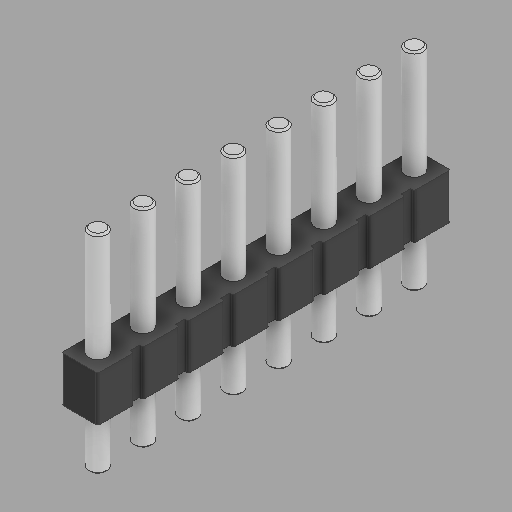
# Autodesk Inventor part: IMU_pin
Saved by Autodesk Inventor 2025 (Build 290162000, 162)
## iProperties
Created: 2024-11-11
Part Number: IMU_pin
Material: 일반
Document SubType Name: Modeling
Designer: OSB
Density: 1 g/cm^3
Appearance: 기본값
Author: OSB
Autodesk Inventor part; units mm, degrees
ref_plane "YZ Plane" through (0, 0, 0) normal (1, 0, 0) x (0, 1, 0)
ref_plane "XZ Plane" through (0, 0, 0) normal (0, 1, 0) x (-1, 0, 0)
ref_plane "XY Plane" through (0, 0, 0) normal (0, 0, 1) x (1, 0, 0)
sketch "스케치1" plane through (0, 0, 0) normal (0, 0, 1) x (1, 0, 0)
  circle A0 centre (0, 0) radius 0.5
  line L0 (0.9, -1) -> (-0.9, -1)
  line L1 (-1, -0.9) -> (-1, 0.9)
  line L2 (-0.9, 1) -> (0.9, 1)
  line L3 (1, 0.9) -> (1, -0.9)
  line L4 (1, -1) -> (-1, 1) construction
  line L5 (-1, -1) -> (1, 1) construction
  arc A1 (-0.9, 1) -> (-1, 0.9) centre (-0.9, 0.9) ccw
  arc A2 (-1, -0.9) -> (-0.9, -1) centre (-0.9, -0.9) ccw
  arc A3 (0.9, -1) -> (1, -0.9) centre (0.9, -0.9) ccw
  arc A4 (1, 0.9) -> (0.9, 1) centre (0.9, 0.9) ccw
  line L6 (-1, -0.8) -> (-1.5, -0.8)
  line L7 (-1, 0.8) -> (-1.5, 0.8)
  line L8 (-1.6, -1) -> (-3.4, -1)
  line L9 (-3.5, 0.8) -> (-4, 0.8)
  arc A5 (-1.6, -1) -> (-1.5, -0.9) centre (-1.6, -0.9) ccw
  arc A6 (-3.5, -0.9) -> (-3.4, -1) centre (-3.4, -0.9) ccw
  circle A7 centre (-2.5, 0) radius 0.5
  line L10 (-3.5, -0.8) -> (-4, -0.8)
  line L11 (-3.5, -0.9) -> (-3.5, 0.9)
  line L12 (-1.5, 0.9) -> (-1.5, -0.9)
  line L13 (-3.4, 1) -> (-1.6, 1)
  arc A8 (-3.4, 1) -> (-3.5, 0.9) centre (-3.4, 0.9) ccw
  arc A9 (-1.5, 0.9) -> (-1.6, 1) centre (-1.6, 0.9) ccw
  line L14 (-1.5, -1) -> (-3.5, 1) construction
  line L15 (-3.5, -1) -> (-1.5, 1) construction
  line L16 (-4.1, -1) -> (-5.9, -1)
  line L17 (-6, 0.8) -> (-6.5, 0.8)
  arc A10 (-4.1, -1) -> (-4, -0.9) centre (-4.1, -0.9) ccw
  arc A11 (-6, -0.9) -> (-5.9, -1) centre (-5.9, -0.9) ccw
  circle A12 centre (-5, 0) radius 0.5
  line L18 (-6, -0.8) -> (-6.5, -0.8)
  line L19 (-6, -0.9) -> (-6, 0.9)
  line L20 (-4, 0.9) -> (-4, -0.9)
  line L21 (-5.9, 1) -> (-4.1, 1)
  arc A13 (-5.9, 1) -> (-6, 0.9) centre (-5.9, 0.9) ccw
  arc A14 (-4, 0.9) -> (-4.1, 1) centre (-4.1, 0.9) ccw
  line L22 (-4, -1) -> (-6, 1) construction
  line L23 (-6, -1) -> (-4, 1) construction
  line L24 (-6.6, -1) -> (-8.4, -1)
  line L25 (-8.5, 0.8) -> (-9, 0.8)
  arc A15 (-6.6, -1) -> (-6.5, -0.9) centre (-6.6, -0.9) ccw
  arc A16 (-8.5, -0.9) -> (-8.4, -1) centre (-8.4, -0.9) ccw
  circle A17 centre (-7.5, 0) radius 0.5
  line L26 (-8.5, -0.8) -> (-9, -0.8)
  line L27 (-8.5, -0.9) -> (-8.5, 0.9)
  line L28 (-6.5, 0.9) -> (-6.5, -0.9)
  line L29 (-8.4, 1) -> (-6.6, 1)
  arc A18 (-8.4, 1) -> (-8.5, 0.9) centre (-8.4, 0.9) ccw
  arc A19 (-6.5, 0.9) -> (-6.6, 1) centre (-6.6, 0.9) ccw
  line L30 (-6.5, -1) -> (-8.5, 1) construction
  line L31 (-8.5, -1) -> (-6.5, 1) construction
  line L32 (-9.1, -1) -> (-10.9, -1)
  line L33 (-11, 0.8) -> (-11.5, 0.8)
  arc A20 (-9.1, -1) -> (-9, -0.9) centre (-9.1, -0.9) ccw
  arc A21 (-11, -0.9) -> (-10.9, -1) centre (-10.9, -0.9) ccw
  circle A22 centre (-10, 0) radius 0.5
  line L34 (-11, -0.8) -> (-11.5, -0.8)
  line L35 (-11, -0.9) -> (-11, 0.9)
  line L36 (-9, 0.9) -> (-9, -0.9)
  line L37 (-10.9, 1) -> (-9.1, 1)
  arc A23 (-10.9, 1) -> (-11, 0.9) centre (-10.9, 0.9) ccw
  arc A24 (-9, 0.9) -> (-9.1, 1) centre (-9.1, 0.9) ccw
  line L38 (-9, -1) -> (-11, 1) construction
  line L39 (-11, -1) -> (-9, 1) construction
  line L40 (-11.6, -1) -> (-13.4, -1)
  line L41 (-13.5, 0.8) -> (-14, 0.8)
  arc A25 (-11.6, -1) -> (-11.5, -0.9) centre (-11.6, -0.9) ccw
  arc A26 (-13.5, -0.9) -> (-13.4, -1) centre (-13.4, -0.9) ccw
  circle A27 centre (-12.5, 0) radius 0.5
  line L42 (-13.5, -0.8) -> (-14, -0.8)
  line L43 (-13.5, -0.9) -> (-13.5, 0.9)
  line L44 (-11.5, 0.9) -> (-11.5, -0.9)
  line L45 (-13.4, 1) -> (-11.6, 1)
  arc A28 (-13.4, 1) -> (-13.5, 0.9) centre (-13.4, 0.9) ccw
  arc A29 (-11.5, 0.9) -> (-11.6, 1) centre (-11.6, 0.9) ccw
  line L46 (-11.5, -1) -> (-13.5, 1) construction
  line L47 (-13.5, -1) -> (-11.5, 1) construction
  line L48 (-14.1, -1) -> (-15.9, -1)
  line L49 (-16, 0.8) -> (-16.5, 0.8)
  arc A30 (-14.1, -1) -> (-14, -0.9) centre (-14.1, -0.9) ccw
  arc A31 (-16, -0.9) -> (-15.9, -1) centre (-15.9, -0.9) ccw
  circle A32 centre (-15, 0) radius 0.5
  line L50 (-16, -0.8) -> (-16.5, -0.8)
  line L51 (-16, -0.9) -> (-16, 0.9)
  line L52 (-14, 0.9) -> (-14, -0.9)
  line L53 (-15.9, 1) -> (-14.1, 1)
  arc A33 (-15.9, 1) -> (-16, 0.9) centre (-15.9, 0.9) ccw
  arc A34 (-14, 0.9) -> (-14.1, 1) centre (-14.1, 0.9) ccw
  line L54 (-14, -1) -> (-16, 1) construction
  line L55 (-16, -1) -> (-14, 1) construction
  line L56 (-16.6, -1) -> (-18.4, -1)
  line L57 (-18.5, 0.8) -> (-19, 0.8) construction
  arc A35 (-16.6, -1) -> (-16.5, -0.9) centre (-16.6, -0.9) ccw
  arc A36 (-18.5, -0.9) -> (-18.4, -1) centre (-18.4, -0.9) ccw
  circle A37 centre (-17.5, 0) radius 0.5
  line L58 (-18.5, -0.8) -> (-19, -0.8) construction
  line L59 (-18.5, -0.9) -> (-18.5, 0.9)
  line L60 (-16.5, 0.9) -> (-16.5, -0.9)
  line L61 (-18.4, 1) -> (-16.6, 1)
  arc A38 (-18.4, 1) -> (-18.5, 0.9) centre (-18.4, 0.9) ccw
  arc A39 (-16.5, 0.9) -> (-16.6, 1) centre (-16.6, 0.9) ccw
  line L62 (-16.5, -1) -> (-18.5, 1) construction
  line L63 (-18.5, -1) -> (-16.5, 1) construction
  dimension "d0" = 1
  dimension "d1" = 2
  dimension "d2" = 2
  dimension "d3" = 0.1
  dimension "d4" = 0.5
  dimension "d5" = 0.5
  dimension "d6" = 0.2
  dimension "d7" = 0.2
  dimension "d10" = 2.5
  constraints: 128 end point, 80 point on line, 64 point on circle, 40 centre point, 8 coincident, 8 tangent, 3 equal radius, 2 horizontal, 2 midpoint, 2 parallel, 2 perpendicular, 1 collinear, 244 other
  measures "d0" diameter of A0
  measures "d1" distance of L4.end L5.end
  measures "d2" distance of L5.start L4.end
  measures "d3" radius of A1
  measures "d4" distance of L6.start L6.end
  measures "d5" distance of L7.start L7.end
  measures "d6" distance between parallel lines of L0 L6
  measures "d7" distance between parallel lines of L2 L7
  measures "d10" distance of L0.end L8.end
extrude "돌출1" add sketch "스케치1" along normal blind 8.5 and the other way blind 3 contours A0 | A7 | A12 | A17 | A22 | A27 | A32 | A37
extrude "돌출2" add sketch "스케치1" along normal blind 2.5 contours A0 | L0 A2 L1 A1 L2 A4 L3 A3 | L6 L12 L7 L1 | L12 A5 L8 A6 L11 A8 L13 A9 | L10 L20 L9 L11 | L20 A10 L16 A11 L19 A13 L21 A14 | L18 L28 L17 L19 | L28 A15 L24 A16 L27 A18 L29 A19 | L26 L36 L25 L27 | L36 A20 L32 A21 L35 A23 L37 A24 | L34 L44 L33 L35 | L44 A25 L40 A26 L43 A28 L45 A29 | L42 L52 L41 L43 | L52 A30 L48 A31 L51 A33 L53 A34 | L50 L60 L49 L51 | L60 A35 L56 A36 L59 A38 L61 A39 | A7 | A12 | A17 | A22 | A27 | A32 | A37
chamfer "모따기1" distance 0.1 angle 45 16 edges at (-0.5, 0, -3) (-3, 0, -3) (-5.5, 0, -3) (-8, 0, -3) (-10.5, 0, -3) (-13, 0, -3) (-15.5, 0, -3) (-18, 0, -3) (-18, 0, 8.5) (-15.5, 0, 8.5) (-13, 0, 8.5) (-10.5, 0, 8.5) (-8, 0, 8.5) (-5.5, 0, 8.5) (-3, 0, 8.5) (-0.5, 0, 8.5)
